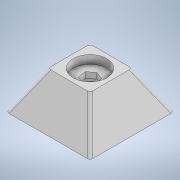
# Autodesk Inventor part: Part1
Saved by Autodesk Inventor 2022.6 (Build 266554000, 554)
## iProperties
Created: 2026-08-11
Part Number: Part1
Material: Generic
Document SubType Name: Modeling
Designer: Dragos Macovei
Density: 1 g/cm^3
Appearance: Default
Author: Dragos Macovei
Autodesk Inventor part; units mm, degrees
ref_plane "YZ Plane" through (0, 0, 0) normal (1, 0, 0) x (0, 1, 0)
ref_plane "XY Plane" through (0, 0, 0) normal (0, 0, 1) x (1, 0, 0)
sketch "Sketch1" plane through (0, 0, 0) normal (0, 1, 0) x (-1, 0, 0)
  line L0 (0, 0) -> (100, 0)
  line L1 (100, 0) -> (100, 100)
  line L2 (100, 100) -> (0, 100)
  line L3 (0, 100) -> (0, 0)
  dimension "d0" = 100
  dimension "d1" = 100
  constraints: 8 end point, 2 parallel, 1 horizontal, 1 perpendicular
  measures "d0" distance of L2.end L1.end
  measures "d1" distance of L1.end L0.end
ref_plane "Work Plane1" through (0, 45, 0) normal (0, 1, 0) x (-1, 0, 0)
sketch "Sketch2" plane through (0, 45, 0) normal (0, 1, 0) x (-1, 0, 0)
  line L0 (75, 75) -> (25, 75)
  line L1 (25, 75) -> (25, 25)
  line L2 (25, 25) -> (75, 25)
  line L3 (75, 25) -> (75, 75)
  point P0 (0, 0)
  point P1 (90.2557, 51.595)
  point P2 (46.6691, 90)
  point P3 (75, 50)
  dimension "d7" = 50
  dimension "d8" = 50
  dimension "d9" = 15
  constraints: 8 end point, 2 parallel, 1 horizontal, 1 midpoint, 1 perpendicular
  measures "d7" distance between parallel lines of L2 L0
  measures "d8" distance between parallel lines of L3 L1
  measures "d9" distance from line of point (46.669, 90) L0
loft "Loft1" add profiles "Sketch2", "Sketch1"
sketch "Sketch3" plane through (-75, 45, 75) normal (0, 1, 0) x (1, 0, 0)
  line L0 (0, 0) -> (50, 0) projected
  line L1 (50, 0) -> (50, 50) projected
  line L2 (50, 50) -> (0, 50) projected
  line L3 (0, 50) -> (0, 0) projected
  circle A0 centre (25, 25) radius 5.15
  point P0 (75, 75)
  dimension "d16" = 10.3
  constraints: 1 centre point
  measures "d16" diameter of A0
extrude "Extrusion1" cut sketch "Sketch3" against normal through all contours A0
sketch "Sketch4" plane through (-75, 45, 75) normal (0, 1, 0) x (1, 0, 0)
  circle A0 centre (25, 25) radius 5.15 projected
  line L0 (0, 0) -> (50, 0) projected
  line L1 (50, 0) -> (50, 50) projected
  line L2 (50, 50) -> (0, 50) projected
  line L3 (0, 50) -> (0, 0) projected
  circle A1 centre (25, 25) radius 5.15 projected
  line L4 (17.2696, 18.7667) -> (15.7366, 28.5781)
  line L5 (15.7366, 28.5781) -> (23.467, 34.8114)
  line L6 (23.467, 34.8114) -> (32.7304, 31.2333)
  line L7 (32.7304, 31.2333) -> (34.2634, 21.4219)
  line L8 (34.2634, 21.4219) -> (26.533, 15.1886)
  line L9 (26.533, 15.1886) -> (17.2696, 18.7667)
  point P0 (75, 75)
  point P1 (19.6018, 31.6947)
  point P2 (30.3982, 18.3053)
  dimension "d19" = 17.2
  dimension "d20" = 19.6228
  constraints: 12 end point, 2 midpoint, 1 coincident, 13 other
  measures "d19" distance of point (19.602, 31.695) point (30.398, 18.305)
  measures "d20" vertical distance of L5.end L8.end
extrude "Extrusion2" cut sketch "Sketch4" against normal blind 17 contours L4 L5 L6 L7 L8 L9
sketch "Sketch5" plane through (-100, 0, 100) normal (0, -1, 0) x (1, 0, 0)
  circle A0 centre (50, -50) radius 5.15 projected
  circle A1 centre (50, -50) radius 20
  point P0 (100, -100)
  dimension "d23" = 40
  constraints: 1 centre point, 1 coincident
  measures "d23" diameter of A1
extrude "Extrusion3" cut sketch "Sketch5" against normal blind 10
sketch "Sketch7" plane through (-50, 10, 50) normal (0, -1, 0) x (1, 0, 0)
  point P0 (50, -50)
sketch "Sketch8" plane through (-50, 10, 50) normal (0, -1, 0) x (1, 0, 0)
  circle A0 centre (0, 0) radius 5.15 projected
  line L0 (-9.2634, -3.5781) -> (-1.533, -9.8114) projected
  line L1 (-9.2634, -3.5781) -> (-7.7304, 6.2333)
  line L2 (-7.7304, 6.2333) -> (1.533, 9.8114)
  line L3 (1.533, 9.8114) -> (9.2634, 3.5781)
  line L4 (9.2634, 3.5781) -> (7.7304, -6.2333)
  line L5 (7.7304, -6.2333) -> (-1.533, -9.8114)
  line L6 (-1.533, -9.8114) -> (-9.2634, -3.5781)
  point P0 (50, -50)
  constraints: 12 end point, 1 coincident, 13 other
extrude "Extrusion5" cut sketch "Sketch8" against normal blind 7
sketch "Sketch9" plane through (-75, 45, 75) normal (0, 1, 0) x (1, 0, 0)
  line L0 (32.7304, 31.2333) -> (34.2634, 21.4219) projected
  line L1 (34.2634, 21.4219) -> (26.533, 15.1886) projected
  line L2 (26.533, 15.1886) -> (17.2696, 18.7667) projected
  line L3 (17.2696, 18.7667) -> (15.7366, 28.5781) projected
  line L4 (15.7366, 28.5781) -> (23.467, 34.8114) projected
  line L5 (23.467, 34.8114) -> (32.7304, 31.2333) projected
  line L6 (0, 0) -> (50, 0) projected
  line L7 (50, 0) -> (50, 50) projected
  line L8 (50, 50) -> (0, 50) projected
  line L9 (0, 50) -> (0, 0) projected
  circle A0 centre (25, 25) radius 5.15 projected
  circle A1 centre (25, 25) radius 20
  point P0 (75, 75)
  constraints: 1 centre point, 1 coincident
extrude "Extrusion6" cut sketch "Sketch9" against normal blind 10 contours L0 L1 L2 L3 L4 L5 | A0 | A1
fillet "Fillet1" radius 4 4 edges at (-87.5, 22.5, 87.5) (-12.5, 22.5, 87.5) (-87.5, 22.5, 12.5) (-12.5, 22.5, 12.5)
body "Solid1"
